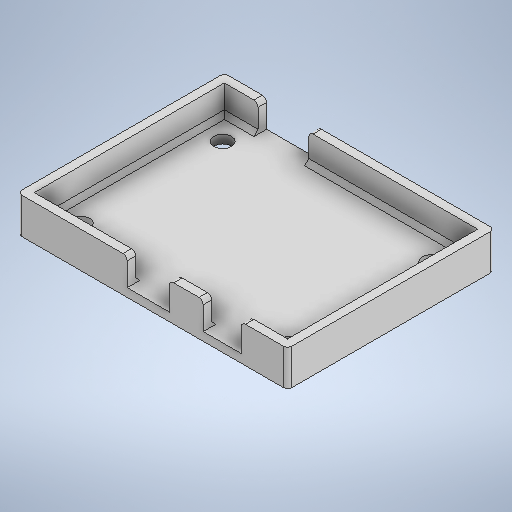
# Autodesk Inventor part: Base_Controlador_Highwonder
Saved by Autodesk Inventor 2025.3 (Build 293356030, 356C)
## iProperties
Created: 2026-04-30
Part Number: Base_Controlador_Highwonder
Material: Generic
Document SubType Name: Modeling
Designer: pablo
Density: 1 g/cm^3
Appearance: Default
Author: pablo
Autodesk Inventor part; units mm, degrees
ref_plane "YZ Plane" through (0, 0, 0) normal (1, 0, 0) x (0, 1, 0)
ref_plane "XZ Plane" through (0, 0, 0) normal (0, 1, 0) x (-1, 0, 0)
ref_plane "XY Plane" through (0, 0, 0) normal (0, 0, 1) x (1, 0, 0)
sketch "Sketch1" plane through (0, 0, 0) normal (0, 1, 0) x (-1, 0, 0)
  line L0 (0, 0) -> (64, 0)
  line L1 (64, 0) -> (64, -49)
  line L2 (64, -49) -> (0, -49)
  line L3 (0, -49) -> (0, 0)
  line L4 (3, -3) -> (61, -3)
  line L5 (61, -3) -> (61, -46)
  line L6 (61, -46) -> (3, -46)
  line L7 (3, -46) -> (3, -3)
  dimension "d0" = 49
  dimension "d1" = 43
  dimension "d2" = 58
  dimension "d3" = 64
  dimension "d4" = 3
  dimension "d5" = 3
  constraints: 16 end point, 4 parallel, 2 horizontal, 2 perpendicular
  measures "d0" distance of L2.end L0.start
  measures "d1" distance of L6.end L4.start
  measures "d2" distance of L5.end L6.end
  measures "d3" distance of L1.end L2.end
  measures "d4" distance between parallel lines of L2 L6
  measures "d5" distance between parallel lines of L3 L7
extrude "Extrusion1" add sketch "Sketch1" along normal blind 2 contours L0 L1 L2 L3 | L4 L5 L6 L7
sketch "Sketch2" plane through (0, 2, 0) normal (0, 1, 0) x (1, 0, 0)
  line L0 (0, 49) -> (-64, 49) projected
  line L1 (0, 0) -> (0, 49) projected
  line L2 (-64, 0) -> (0, 0) projected
  line L3 (-64, 49) -> (-64, 0) projected
  line L4 (-61, 3) -> (-61, 46) construction
  line L5 (-3, 3) -> (-61, 3) projected
  line L6 (-61, 46) -> (-3, 46) projected
  line L7 (-3, 46) -> (-3, 3) projected
  line L8 (-2, 47) -> (-62, 47)
  line L9 (-62, 47) -> (-62, 2)
  line L10 (-62, 2) -> (-2, 2)
  line L11 (-2, 2) -> (-2, 47)
  dimension "d8" = 2
  dimension "d9" = 2
  dimension "d10" = 2
  dimension "d11" = 2
  constraints: 8 end point, 2 parallel, 1 horizontal, 1 perpendicular
  measures "d8" distance between parallel lines of L11 L1
  measures "d9" distance between parallel lines of L2 L10
  measures "d10" distance between parallel lines of L3 L9
  measures "d11" distance between parallel lines of L0 L8
extrude "Extrusion2" add sketch "Sketch2" along normal blind 6.5
sketch "Sketch3" plane through (0, 2, 0) normal (0, 1, 0) x (1, 0, 0)
  line L0 (-3, 46) -> (-3, 3) projected
  line L1 (-61, 46) -> (-3, 46) projected
  line L2 (-3, 3) -> (-61, 3) projected
  line L3 (-61, 3) -> (-61, 46) projected
  line L4 (0, 49) -> (-64, 49) projected
  line L5 (0, 0) -> (0, 49) projected
  line L6 (-64, 0) -> (0, 0) projected
  line L7 (-64, 49) -> (-64, 0) projected
  point P0 (-7.3, 7.7)
  point P1 (-56.7, 7.7)
  point P2 (-56.7, 41.3)
  point P3 (-7.3, 41.3)
  dimension "d14" = 4.3
  dimension "d15" = 4.3
  dimension "d16" = 4.7
  dimension "d17" = 4.7
  constraints: 2 horizontal alignment, 2 vertical alignment
  measures "d14" distance from line of point (-7.3, 7.7) L0
  measures "d15" distance from line of L3 point (-56.7, 41.3)
  measures "d16" distance from line of L2 point (-7.3, 7.7)
  measures "d17" distance from line of L1 point (-7.3, 41.3)
hole "Hole1" at (-7.3, 2, -7.7) at (-7.3, 2, -41.3) at (-56.7, 2, -41.3) at (-56.7, 2, -7.7) direction (0, -1, 0) diameter 4.2 end through all
sketch "Sketch4" plane through (0, 0, -49) normal (0, 0, -1) x (-1, 0, 0)
  line L0 (54, 8.5) -> (54, 2)
  line L1 (0, 8.5) -> (64, 8.5) projected
  line L2 (0, 0) -> (64, 0) projected
  line L3 (64, 0) -> (64, 8.5) projected
  line L4 (0, 8.5) -> (64, 8.5) projected
  line L5 (0, 0) -> (0, 8.5) projected
  line L6 (2, 2) -> (62, 2) projected
  line L7 (42, 8.5) -> (42, 2)
  point P0 (0, 0)
  dimension "d25" = 10
  dimension "d26" = 22
  constraints: 4 end point, 4 point on line, 1 perpendicular, 1 vertical
  measures "d25" distance between parallel lines of L0 L3
  measures "d26" distance between parallel lines of L3 L7
extrude "Extrusion3" cut sketch "Sketch4" against normal up to surface (2 mm away) contours L0 L6 L7 L1
sketch "Sketch5" plane through (-64, 0, 0) normal (0, 0, 1) x (1, 0, 0)
  line L0 (0, 0) -> (64, 0) projected
  line L1 (64, 0) -> (64, 8.5) projected
  line L2 (0, 8.5) -> (64, 8.5) projected
  line L3 (0, 0) -> (0, 8.5) projected
  line L4 (2, 2) -> (62, 2) projected
  line L5 (26, 8.5) -> (26, 2)
  line L6 (36, 8.5) -> (36, 2)
  line L7 (62, 8.5) -> (2, 8.5) projected
  line L8 (53, 8.5) -> (53, 2)
  line L9 (44, 2) -> (44, 8.5)
  dimension "d29" = 26
  dimension "d31" = 36
  dimension "d32" = 11
  dimension "d33" = 20
  constraints: 8 end point, 8 point on line, 4 perpendicular
  measures "d29" distance between parallel lines of L3 L5
  measures "d31" distance between parallel lines of L3 L6
  measures "d32" distance between parallel lines of L1 L8
  measures "d33" distance between parallel lines of L1 L9
extrude "Extrusion4" cut sketch "Sketch5" against normal up to surface (2 mm away) contours L2 L6 L4 L5 | L8 L4 L9 L2
fillet "Fillet1" radius 1 6 edges at (-28, 8.5, -1) (-38, 8.5, -1) (-11, 8.5, -1) (-20, 8.5, -1) (-42, 8.5, -48) (-54, 8.5, -48)
chamfer "Chamfer1" distance 1 angle 45 7 edges at (-22, 2, -47) (-2, 2, -24.5) (-6.5, 2, -2) (-24, 2, -2) (-50, 2, -2) (-58, 2, -47) (-62, 2, -24.5)
fillet "Fillet2" radius 1 4 edges at (0, 4.25, -49) (-64, 4.25, -49) (-64, 4.25, 0) (0, 4.25, 0)
sketch "Sketch6" plane through (0, 0, 0) normal (0, -1, 0) x (1, 0, 0)
  circle A0 centre (-7.3, -7.7) radius 2.1 projected
  circle A1 centre (-7.3, -41.3) radius 2.1 projected
  circle A2 centre (-56.7, -41.3) radius 2.1 projected
  circle A3 centre (-56.7, -7.7) radius 2.1 projected
  arc A4 (0, -1) -> (-1, 0) centre (-1, -1) ccw projected
  line L0 (-63, 0) -> (-1, 0) projected
  arc A5 (-63, 0) -> (-64, -1) centre (-63, -1) ccw projected
  line L1 (-64, -48) -> (-64, -1) projected
  arc A6 (-64, -48) -> (-63, -49) centre (-63, -48) ccw projected
  line L2 (-1, -49) -> (-63, -49) projected
  arc A7 (-1, -49) -> (0, -48) centre (-1, -48) ccw projected
  line L3 (0, -1) -> (0, -48) projected
  line L4 (-42, -14.5) -> (-22, -14.5)
  line L5 (-22, -14.5) -> (-22, -34.5)
  line L6 (-22, -34.5) -> (-42, -34.5)
  line L7 (-42, -34.5) -> (-42, -14.5)
  point P0 (0, 0)
  point P1 (-22, -24.5)
  point P2 (0, -24.5)
  point P3 (-32, -14.5)
  point P4 (-32, 0)
  dimension "d41" = 20
  constraints: 8 end point, 4 midpoint, 2 parallel, 2 perpendicular, 1 horizontal, 1 horizontal alignment, 1 vertical alignment
  measures "d41" distance of L5.end L6.end
extrude "Extrusion5" add sketch "Sketch6" along normal blind 10 contours L4 L5 L6 L7
fillet "Fillet3" radius 3 4 edges at (-22, 0, -24.5) (-32, 0, -34.5) (-42, 0, -24.5) (-32, 0, -14.5)
equation "\"d4\" = -0.5 * d1 + 0.5 * d0"
equation "\"d5\" = -0.5 * d2 + 0.5 * d3"
body "Solid1"
